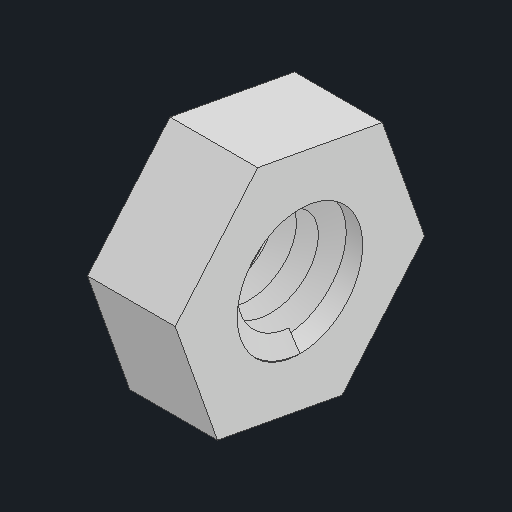
# Autodesk Inventor part: Spacer_for_shaft_Second_top
Saved by Autodesk Inventor 2027.1 (Build 311270010, 270A)
## iProperties
Created: 2026-11-03
Part Number: Spacer_for_shaft_Second_top
Material: 一般
Document SubType Name: Modeling
Designer: takuya
Density: 1 g/cm^3
Appearance: 既定
Author: takuya
Autodesk Inventor part; units mm, degrees
ref_plane "YZ Plane" through (0, 0, 0) normal (1, 0, 0) x (0, 1, 0)
ref_plane "XZ Plane" through (0, 0, 0) normal (0, 1, 0) x (-1, 0, 0)
sketch "スケッチ3" plane through (0, 0, 0) normal (0, 0, 1) x (1, 0, 0)
  spline S0 degree 3 poles (0.7, 153.6229) (0.6578, 153.6229) (0.6156, 153.1524) (0.5735, 152.4657) (0.5315, 151.7826) (0.4895, 150.9208) (0.4476, 150.3422) (0.405, 149.7547) (0.3624, 149.4911) (0.3198, 149.6962) (0.2777, 149.8987) (0.2356, 150.5467) (0.1935, 151.2915) (0.1512, 152.0409) (0.1089, 152.849) (0.0666, 153.2765) (0.0444, 153.5005) (0.0222, 153.6229) (0, 153.6229) knots -6.283185 -6.283185 -6.283185 -6.283185 -5.147373 -5.147373 -5.147373 -4.017394 -4.017394 -4.017394 -2.870129 -2.870129 -2.870129 -1.737258 -1.737258 -1.737258 -0.597451 -0.597451 -0.597451 0 0 0 0 projected
  spline S1 degree 3 poles (0.7, 153.6229) (0.7425, 153.6229) (0.7849, 153.1458) (0.8274, 152.4523) (0.8698, 151.7591) (0.9122, 150.8868) (0.9547, 150.3116) (0.9971, 149.7366) (1.0395, 149.4893) (1.0819, 149.7044) (1.1243, 149.9195) (1.1667, 150.5853) (1.2091, 151.3387) (1.2515, 152.0919) (1.2939, 152.8925) (1.3363, 153.3045) (1.3786, 153.7162) (1.421, 153.7177) (1.4634, 153.3081) (1.5057, 152.8987) (1.5481, 152.1003) (1.5904, 151.3473) (1.6327, 150.5946) (1.6751, 149.9272) (1.7174, 149.708) (1.7597, 149.4888) (1.802, 149.729) (1.8443, 150.2981) (1.8866, 150.867) (1.9289, 151.7344) (1.9712, 152.4293) (2.0135, 153.1239) (2.0558, 153.6095) (2.0981, 153.6226) (2.1403, 153.6357) (2.1826, 153.176) (2.2249, 152.4928) (2.2671, 151.8098) (2.3094, 150.9394) (2.3516, 150.3533) (2.3939, 149.7675) (2.4361, 149.4965) (2.4783, 149.6872) (2.5205, 149.8778) (2.5628, 150.5197) (2.605, 151.2654) (2.6472, 152.0108) (2.6894, 152.821) (2.7316, 153.2575) (2.7738, 153.6939) (2.816, 153.7342) (2.8582, 153.3566) (2.9003, 152.9792) (2.9425, 152.2038) (2.9847, 151.4496) (3.0268, 150.6956) (3.069, 150.002) (3.1111, 149.7433) (3.1533, 149.4848) (3.1954, 149.6743) (3.2376, 150.2096) (3.2797, 150.7448) (3.3218, 151.5976) (3.364, 152.3082) (3.4061, 153.0184) (3.4482, 153.5496) (3.4903, 153.6154) (3.5324, 153.681) (3.5745, 153.2782) (3.6166, 152.6239) (3.6587, 151.9697) (3.7008, 151.0982) (3.7429, 150.4785) (3.7849, 149.8591) (3.827, 149.5234) (3.8691, 149.6522) (3.9111, 149.7809) (3.9532, 150.3671) (3.9953, 151.0954) (4.0373, 151.8235) (4.0794, 152.6561) (4.1214, 153.1455) (4.1634, 153.6348) (4.2055, 153.7559) (4.2475, 153.4439) (4.2895, 153.1319) (4.3315, 152.403) (4.3736, 151.6487) (4.4156, 150.8946) (4.4576, 150.1539) (4.4996, 149.8242) (4.5416, 149.4946) (4.5836, 149.5926) (4.6256, 150.0657) (4.6676, 150.5386) (4.7095, 151.3621) (4.7515, 152.0945) (4.7935, 152.8267) (4.8355, 153.4304) (4.8774, 153.582) (4.9194, 153.7336) (4.9613, 153.4256) (5.0033, 152.823) (5.0452, 152.2206) (5.0872, 151.3546) (5.1291, 150.6888) (5.1711, 150.0231) (5.213, 149.5915) (5.2549, 149.6249) (5.2969, 149.6583) (5.3388, 150.1548) (5.3807, 150.8487) (5.4226, 151.5424) (5.4645, 152.3981) (5.5064, 152.9583) (5.5483, 153.5182) (5.5902, 153.7543) (5.6321, 153.5402) (5.6757, 153.3176) (5.7193, 152.6176) (5.7629, 151.8398) (5.8059, 151.073) (5.8488, 150.2746) (5.8918, 149.8897) (5.9347, 149.5052) (5.9776, 149.5548) (6.0206, 150.0108) (6.0625, 150.4563) (6.1044, 151.2652) (6.1464, 152.0043) (6.1892, 152.7591) (6.232, 153.4003) (6.2749, 153.5722) (6.3177, 153.7441) (6.3604, 153.4382) (6.4032, 152.8241) (6.446, 152.2105) (6.4887, 151.3231) (6.5315, 150.6522) (6.5742, 149.9819) (6.6169, 149.5645) (6.6596, 149.6303) (6.7022, 149.696) (6.7449, 150.2402) (6.7876, 150.9632) (6.8302, 151.6855) (6.8728, 152.5469) (6.9154, 153.0736) (6.958, 153.5998) (7.0006, 153.7635) (7.0432, 153.4747) (7.0857, 153.1862) (7.1282, 152.4617) (7.1708, 151.6985) (7.2133, 150.936) (7.2558, 150.1759) (7.2983, 149.8344) (7.3408, 149.4932) (7.3832, 149.5881) (7.4257, 150.0672) (7.4681, 150.5459) (7.5106, 151.3825) (7.553, 152.1203) (7.5954, 152.8575) (7.6378, 153.4568) (7.6802, 153.5914) (7.7226, 153.7259) (7.7649, 153.3894) (7.8073, 152.7652) (7.8496, 152.1415) (7.8919, 151.2635) (7.9343, 150.6086) (7.9766, 149.9542) (8.0188, 149.5571) (8.0611, 149.6329) (8.1034, 149.7087) (8.1457, 150.2526) (8.1879, 150.9697) (8.2302, 151.6862) (8.2724, 152.5381) (8.3146, 153.0638) (8.3568, 153.5892) (8.399, 153.7615) (8.4412, 153.4876) (8.4834, 153.2138) (8.5256, 152.5087) (8.5677, 151.7533) (8.6099, 150.9984) (8.652, 150.2325) (8.6942, 149.869) (8.7363, 149.5057) (8.7784, 149.563) (8.8205, 150.0101) (8.8626, 150.4569) (8.9047, 151.2697) (8.9467, 152.0108) (8.9888, 152.7515) (9.0309, 153.3824) (9.0729, 153.5641) (9.1149, 153.7457) (9.157, 153.4695) (9.199, 152.8838) (9.241, 152.2984) (9.283, 151.4341) (9.325, 150.7548) (9.367, 150.0759) (9.409, 149.6165) (9.451, 149.623) (9.4929, 149.6295) (9.5349, 150.101) (9.5768, 150.7849) (9.6188, 151.4684) (9.6607, 152.3291) (9.7026, 152.9064) (9.7445, 153.4834) (9.7864, 153.7479) (9.8284, 153.5585) (9.8718, 153.3621) (9.9153, 152.686) (9.9587, 151.9142) (10.0016, 151.1521) (10.0445, 150.3401) (10.0874, 149.93) (10.1303, 149.5207) (10.1731, 149.5341) (10.2159, 149.9629) (10.2586, 150.3907) (10.3014, 151.2085) (10.3441, 151.9644) (10.3868, 152.7189) (10.4294, 153.3705) (10.4721, 153.5604) (10.5146, 153.75) (10.5572, 153.4695) (10.5998, 152.8728) (10.6423, 152.2773) (10.6848, 151.3989) (10.7273, 150.7185) (10.7697, 150.0392) (10.8121, 149.5935) (10.8546, 149.6246) (10.8969, 149.6557) (10.9393, 150.1602) (10.9816, 150.8636) (11.0239, 151.5659) (11.0662, 152.4293) (11.1085, 152.9851) (11.1507, 153.5401) (11.1929, 153.7594) (11.2351, 153.5242) (11.2773, 153.2894) (11.3195, 152.6137) (11.3616, 151.8623) (11.4037, 151.1118) (11.4458, 150.3247) (11.488, 149.9252) (11.53, 149.5261) (11.5721, 149.5342) (11.6141, 149.945) (11.6561, 150.3553) (11.6981, 151.1462) (11.7401, 151.8932) (11.7821, 152.6394) (11.824, 153.3037) (11.866, 153.5303) (11.9079, 153.7566) (11.9498, 153.5347) (11.9917, 152.9833) (12.0337, 152.4306) (12.0757, 151.575) (12.1177, 150.8757) (12.1604, 150.1643) (12.2031, 149.6531) (12.2458, 149.6243) (12.2884, 149.5957) (12.3309, 150.0472) (12.3735, 150.7311) (12.4159, 151.4126) (12.4583, 152.2883) (12.5007, 152.8803) (12.543, 153.4705) (12.5853, 153.7479) (12.6276, 153.562) (12.6697, 153.3766) (12.7119, 152.7404) (12.754, 151.997) (12.7961, 151.2556) (12.8381, 150.4459) (12.8802, 150.0031) (12.9221, 149.5615) (12.9641, 149.5076) (13.006, 149.8703) (13.0489, 150.2409) (13.0917, 151.0282) (13.1346, 151.7948) (13.1771, 152.5556) (13.2197, 153.2546) (13.2622, 153.5088) (13.3044, 153.7614) (13.3467, 153.5619) (13.3889, 153.0187) (13.431, 152.4783) (13.473, 151.6262) (13.515, 150.9199) (13.5578, 150.2006) (13.6006, 149.6718) (13.6434, 149.6264) (13.6856, 149.5816) (13.7278, 150.0083) (13.77, 150.6756) (13.8127, 151.3502) (13.8554, 152.2348) (13.898, 152.842) (13.932, 153.3258) (13.966, 153.6229) (14, 153.6229) knots 0 0 0 0 1.143178 1.143178 1.143178 2.285869 2.285869 2.285869 3.428081 3.428081 3.428081 4.569817 4.569817 4.569817 5.711083 5.711083 5.711083 6.851884 6.851884 6.851884 7.992226 7.992226 7.992226 9.132114 9.132114 9.132114 10.271552 10.271552 10.271552 11.410547 11.410547 11.410547 12.549103 12.549103 12.549103 13.687225 13.687225 13.687225 14.824919 14.824919 14.824919 15.962189 15.962189 15.962189 17.099041 17.099041 17.099041 18.23548 18.23548 18.23548 19.37151 19.37151 19.37151 20.507137 20.507137 20.507137 21.642366 21.642366 21.642366 22.777202 22.777202 22.777202 23.911649 23.911649 23.911649 25.045713 25.045713 25.045713 26.179399 26.179399 26.179399 27.312711 27.312711 27.312711 28.445655 28.445655 28.445655 29.578235 29.578235 29.578235 30.710456 30.710456 30.710456 31.842323 31.842323 31.842323 32.97384 32.97384 32.97384 34.105014 34.105014 34.105014 35.235848 35.235848 35.235848 36.366347 36.366347 36.366347 37.496516 37.496516 37.496516 38.62636 38.62636 38.62636 39.755884 39.755884 39.755884 40.885092 40.885092 40.885092 42.013988 42.013988 42.013988 43.142579 43.142579 43.142579 44.270868 44.270868 44.270868 45.444456 45.444456 45.444456 46.601439 46.601439 46.601439 47.757176 47.757176 47.757176 48.886545 48.886545 48.886545 50.039887 50.039887 50.039887 51.192054 51.192054 51.192054 52.343069 52.343069 52.343069 53.492953 53.492953 53.492953 54.641731 54.641731 54.641731 55.789425 55.789425 55.789425 56.936056 56.936056 56.936056 58.081647 58.081647 58.081647 59.22622 59.22622 59.22622 60.369795 60.369795 60.369795 61.512396 61.512396 61.512396 62.654043 62.654043 62.654043 63.794756 63.794756 63.794756 64.934558 64.934558 64.934558 66.073469 66.073469 66.073469 67.211509 67.211509 67.211509 68.348699 68.348699 68.348699 69.485059 69.485059 69.485059 70.620609 70.620609 70.620609 71.75537 71.75537 71.75537 72.889361 72.889361 72.889361 74.022601 74.022601 74.022601 75.155111 75.155111 75.155111 76.28691 76.28691 76.28691 77.418018 77.418018 77.418018 78.548452 78.548452 78.548452 79.678234 79.678234 79.678234 80.80738 80.80738 80.80738 81.935912 81.935912 81.935912 83.106056 83.106056 83.106056 84.261548 84.261548 84.261548 85.414627 85.414627 85.414627 86.565388 86.565388 86.565388 87.713921 87.713921 87.713921 88.860316 88.860316 88.860316 90.004662 90.004662 90.004662 91.147045 91.147045 91.147045 92.287549 92.287549 92.287549 93.426259 93.426259 93.426259 94.563257 94.563257 94.563257 95.698625 95.698625 95.698625 96.832441 96.832441 96.832441 97.964785 97.964785 97.964785 99.095735 99.095735 99.095735 100.225367 100.225367 100.225367 101.353757 101.353757 101.353757 102.484668 102.484668 102.484668 103.635086 103.635086 103.635086 104.781162 104.781162 104.781162 105.923248 105.923248 105.923248 107.061684 107.061684 107.061684 108.196801 108.196801 108.196801 109.328918 109.328918 109.328918 110.458345 110.458345 110.458345 111.612603 111.612603 111.612603 112.757924 112.757924 112.757924 113.895719 113.895719 113.895719 115.027304 115.027304 115.027304 116.179785 116.179785 116.179785 117.316275 117.316275 117.316275 118.465214 118.465214 118.465214 119.380521 119.380521 119.380521 119.380521 projected
  line L0 (0.3563, 149.6319) -> (1.0563, 149.6297)
  line L1 (1.0563, 149.6297) -> (1.0563, 149.6297)
  line L2 (1.0563, 149.6297) -> (0.7, 150.1596)
  line L3 (0.7, 150.1596) -> (0.3563, 149.6319)
  point P0 (0, 0)
  dimension "d2" = 0.7
  constraints: 8 end point, 2 other
  measures "d2" distance of L0.start L0.end
coil "コイル1" sketch "スケッチ3" operation add axis through (2.8, 151.6229, 0) along (1, 0, 0) pitch 0.7 turns 3 hand right contours L3 L2 S1 L0 | L2 S1
ref_plane "作業平面4" through (0, 151.6229, 0) normal (-1, 0, 0) x (0, 0.3331321, -0.9428802)
sketch "スケッチ4" plane through (0, 151.6229, 0) normal (-1, 0, 0) x (0, 0.3331321, -0.9428802)
  circle A0 centre (0, 0) radius 2 projected
  line L0 (-3.5, 2.0207) -> (0, 4.0415)
  line L1 (0, 4.0415) -> (3.5, 2.0207)
  line L2 (3.5, 2.0207) -> (3.5, -2.0207)
  line L3 (3.5, -2.0207) -> (0, -4.0415)
  line L4 (0, -4.0415) -> (-3.5, -2.0207)
  line L5 (-3.5, -2.0207) -> (-3.5, 2.0207)
  point P0 (-50.5105, 142.9622)
  dimension "d11" = 7
  constraints: 12 end point, 1 coincident, 13 other
  measures "d11" distance between parallel lines of L2 L5
extrude "押し出し1" add sketch "スケッチ4" against normal up to surface (3.1563 mm away)
sketch "スケッチ5" plane through (0, 151.6229, 0) normal (-1, 0, 0) x (0, 0.3331321, -0.9428802)
  line L0 (-3.5, -2.0207) -> (0, -4.0415) projected
  line L1 (0, -4.0415) -> (3.5, -2.0207) projected
  line L2 (3.5, -2.0207) -> (3.5, 2.0207) projected
  line L3 (3.5, 2.0207) -> (0, 4.0415) projected
  line L4 (0, 4.0415) -> (-3.5, 2.0207) projected
  line L5 (-3.5, 2.0207) -> (-3.5, -2.0207) projected
  circle A0 centre (0, 0) radius 2 projected
  point P0 (-50.5105, 142.9622)
extrude "押し出し2" cut sketch "スケッチ5" against normal blind 0.36 contours L5 L4 L3 L2 L1 L0 | A0
